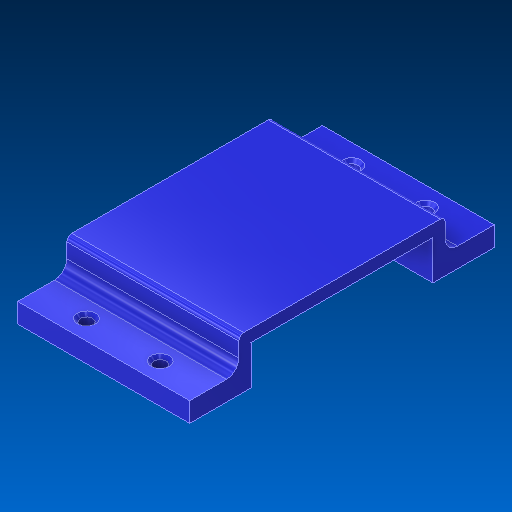
# Autodesk Inventor part: Pump Holder
Saved by Autodesk Inventor 2019 (Build 230136000, 136)
## iProperties
Created: 2019-03-13
Part Number: Pump Holder
Material: Generic
Document SubType Name: Modeling
Designer: Dell
Density: 1 g/cm^3
Appearance: Blue - Wall Paint - Glossy
Mass: 62.9453 g
Surface Area: 242.451 cm^2
Volume: 62.9453 cm^3
Author: Dell
Autodesk Inventor part; units mm, degrees
ref_plane "YZ Plane" through (0, 0, 0) normal (1, 0, 0) x (0, 1, 0)
ref_plane "XZ Plane" through (0, 0, 0) normal (0, 1, 0) x (-1, 0, 0)
ref_plane "XY Plane" through (0, 0, 0) normal (0, 0, 1) x (1, 0, 0)
sketch "Sketch1" plane through (0, 0, 0) normal (1, 0, 0) x (0, 1, 0)
  line L0 (-16.6324, -8.9861) -> (-16.6324, -50.9861)
  line L1 (-16.6324, -50.9861) -> (-29.6324, -50.9861)
  line L2 (-29.6324, -50.9861) -> (-29.6324, -70.9861)
  line L3 (-29.6324, -70.9861) -> (-37.6324, -70.9861)
  line L4 (-37.6324, -45.9861) -> (-2.232, -45.9861)
  line L5 (47.4371, -8.9861) -> (-53.9683, -8.9861)
  line L6 (-21.6324, 28.0139) -> (-21.6324, -45.9861)
  line L7 (-21.6324, -45.9861) -> (-3.1938, -45.9861)
  line L8 (-16.6324, -50.9861) -> (-16.6324, 33.0139)
  line L9 (-16.6324, 33.0139) -> (-29.6324, 33.0139)
  line L10 (-29.6324, 33.0139) -> (-29.6324, 53.0139)
  line L11 (-29.6324, 53.0139) -> (-37.6324, 53.0139)
  line L12 (-37.6324, 28.0139) -> (-21.6324, 28.0139)
  line L13 (-16.6324, -50.9861) -> (-16.6324, -8.9861)
  line L14 (-16.6324, -50.9861) -> (-29.6324, -50.9861)
  line L15 (-29.6324, -50.9861) -> (-29.6324, -70.9861)
  line L16 (-29.6324, -70.9861) -> (-37.6324, -70.9861)
  line L17 (-37.6324, -45.9861) -> (-2.232, -45.9861)
  line L18 (-21.6324, -8.9861) -> (-21.6324, -45.9861)
  line L19 (-21.6324, -45.9861) -> (-3.1938, -45.9861)
  line L20 (-37.6324, 53.0139) -> (-37.6324, 28.0139)
  line L21 (-37.6324, 53.0139) -> (-37.6324, 28.0139)
  line L22 (-37.6324, 53.0139) -> (-37.6324, 28.0139)
  line L23 (-37.6324, -45.9861) -> (-37.6324, -70.9861)
  point P0 (0, 0)
  point P1 (-16.6324, 33.0139)
  point P2 (-2.232, 28.0139)
  dimension "d4" = 5
  dimension "d6" = 5
  dimension "d12" = 84
  dimension "d22" = 8
  dimension "d23" = 16
  constraints: 48 end point, 11 symmetric about line, 7 point on line, 4 perpendicular, 2 midpoint, 2 vertical, 1 horizontal
  measures "d4" distance between parallel lines of L4 L1
  measures "d6" distance between parallel lines of L6 L0
  measures "d12" distance between parallel lines of L9 L1
  measures "d22" distance of L2.end L3.end
  measures "d23" distance between parallel lines of L21 L18
extrude "Extrusion1" add sketch "Sketch1" along normal blind 70
fillet "Fillet1" radius 5 1 edges at (35, -29.6324, 33.0139)
fillet "Fillet2" radius 5 1 edges at (35, -29.6324, -50.9861)
fillet "Fillet3" radius 2 2 edges at (35, -16.6324, -50.9861) (35, -16.6324, 33.0139)
sketch "Sketch4" plane through (0, -29.6324, 53.0139) normal (0, 1, 0) x (1, 0, 0)
  circle A0 centre (50, 8) radius 4 projected
  circle A1 centre (20, 8) radius 4 projected
  circle A2 centre (50, 116) radius 3.75 projected
  circle A3 centre (20, 116) radius 4 projected
  point P0 (0, 53.0139)
hole "Hole1" at (50, -29.6324, 45.0139) at (20, -29.6324, 45.0139) at (20, -29.6324, -62.9861) at (50, -29.6324, -62.9861) direction (0, -1, 0) diameter 5 end through all countersink diameter 7.5 countersink angle 90
body "Solid1"
